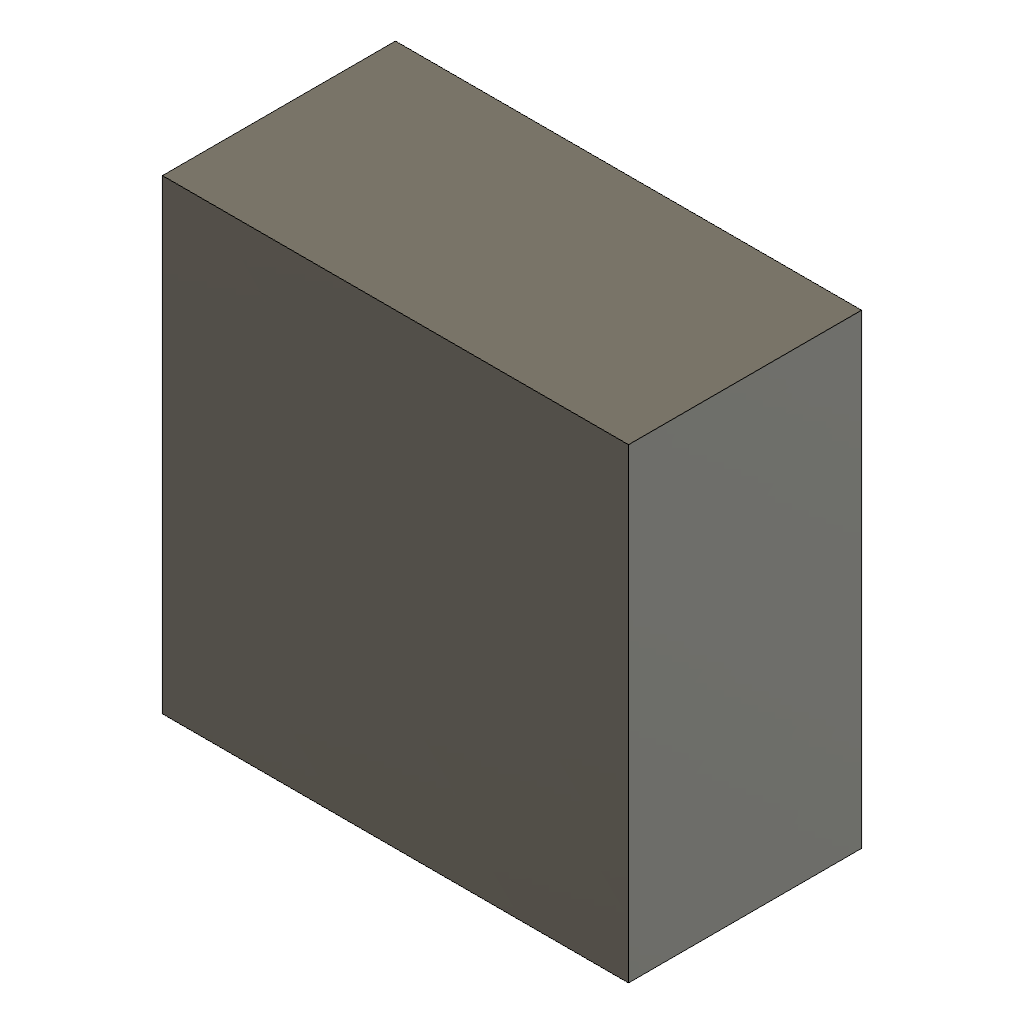
rectangle_overlap (Autodesk Fusion 360 design; units mm, degrees)
part number: 2026-10-21-11-21-44-580
Autodesk Fusion 360 part; units mm, degrees
sketch "TrimmedProfileSources" plane through (0, 0, 0) normal (0, 0, 1) x (1, 0, 0)
  line L0 (0, 0) -> (40, 0)
  line L1 (40, 0) -> (40, 30)
  line L2 (40, 30) -> (0, 30)
  line L3 (0, 30) -> (0, 0)
  line L4 (20, -10) -> (50, -10)
  line L5 (50, -10) -> (50, 20)
  line L6 (50, 20) -> (20, 20)
  line L7 (20, 20) -> (20, -10)
extrude "SelectedTrimmedProfile" add sketch "TrimmedProfileSources" along normal blind 10 contours L0 L1 L6 L7
